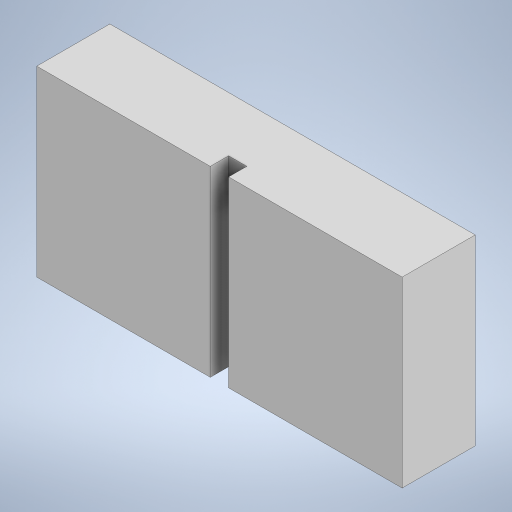
# Autodesk Inventor part: oko
Saved by Autodesk Inventor 2024 (Build 280153000, 153)
## iProperties
Created: 2025-11-04
Part Number: oko
Material: Všeobecné
Document SubType Name: Modeling
Designer: zak
Density: 1 g/cm^3
Appearance: Výchozí
Author: zak
Autodesk Inventor part; units mm, degrees
ref_plane "YZ Plane" through (0, 0, 0) normal (1, 0, 0) x (0, 1, 0)
ref_plane "XZ Plane" through (0, 0, 0) normal (0, 1, 0) x (-1, 0, 0)
ref_plane "XY Plane" through (0, 0, 0) normal (0, 0, 1) x (1, 0, 0)
sketch "Náčrt1" plane through (0, 0, 0) normal (0, 0, 1) x (1, 0, 0)
  line L0 (0, -2) -> (0, 12) projected
  line L1 (-18, 0) -> (3, 0) projected
  line L2 (-15, 10) -> (-5, 10)
  line L3 (-5, 10) -> (-5, 5)
  line L4 (-5, 5) -> (-15, 5)
  line L5 (-15, 5) -> (-15, 10)
  point P0 (0, 0)
  dimension "d0" = 10
  dimension "d1" = 5
  dimension "d2" = 5
  dimension "d3" = 5
  constraints: 8 end point, 2 parallel, 1 horizontal, 1 perpendicular
  measures "d0" distance of L3.end L4.end
  measures "d1" distance of L2.end L3.end
  measures "d2" distance between parallel lines of L0 L3
  measures "d3" distance between parallel lines of L1 L4
extrude "Vysunutí1" add sketch "Náčrt1" along normal blind 2
sketch "Náčrt3" plane through (0, 0, 2) normal (0, 0, 1) x (1, 0, 0)
  line L0 (-15, 5) -> (-5, 5) projected
  line L1 (-10.25, 5) -> (-9.75, 5)
  line L2 (-9.75, 5) -> (-9.75, 10)
  line L3 (-9.75, 10) -> (-10.25, 10)
  line L4 (-10.25, 10) -> (-10.25, 5)
  line L5 (-5, 5) -> (-5, 10) projected
  line L6 (-15, 10) -> (-15, 5) projected
  point P0 (0, 0)
  dimension "d14" = 0.5
  dimension "d15" = 5
  dimension "d16" = 4.75
  constraints: 8 end point, 2 parallel, 1 horizontal, 1 perpendicular, 1 point on line
  measures "d14" distance of L3.end L2.end
  measures "d15" distance of L2.end L1.end
  measures "d16" distance between parallel lines of L5 L2
emboss "Reliéf1" sketch "Náčrt3" operation cut depth 0.5 direction (0, 0, -1)
